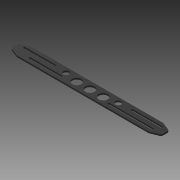
# Autodesk Inventor part: collecive_support_1
Saved by Autodesk Inventor 2015 (Build 190159000, 159)
## iProperties
Created: 2022-11-07
Part Number: collecive_support_1
Material: Generic
Document SubType Name: Modeling
Designer: Pavel Brodský
Density: 1 g/cm^3
Appearance: Default
Author: Pavel Brodský
Autodesk Inventor part; units mm, degrees
ref_plane "YZ Plane" through (0, 0, 0) normal (1, 0, 0) x (0, 1, 0)
ref_plane "XZ Plane" through (0, 0, 0) normal (0, 1, 0) x (-1, 0, 0)
ref_plane "XY Plane" through (0, 0, 0) normal (0, 0, 1) x (1, 0, 0)
sketch "Náčrt1" plane through (0, 0, 0) normal (0, 0, 1) x (1, 0, 0)
  line L0 (25.9629, 0) -> (384.0371, 0)
  line L1 (410, 13.3852) -> (410, 26.6148)
  line L2 (384.0371, 40) -> (25.9629, 40)
  line L3 (0, 26.6148) -> (0, 13.3852)
  line L4 (24.106, 39.6424) -> (3.143, 31.2572)
  line L5 (24.106, 0.3576) -> (3.143, 8.7428)
  line L6 (385.894, 0.3576) -> (406.857, 8.7428)
  line L7 (385.894, 39.6424) -> (406.857, 31.2572)
  line L8 (205, 0) -> (205, 122.739) construction
  line L9 (0, 20) -> (410, 20) construction
  circle A0 centre (205, 20) radius 12.5
  circle A1 centre (241, 20) radius 12.5
  circle A2 centre (169, 20) radius 12.5
  circle A3 centre (134, 26) radius 8
  circle A4 centre (276, 26) radius 8
  arc A5 (385.894, 39.6424) -> (384.0371, 40) centre (384.0371, 35) ccw
  arc A6 (410, 26.6148) -> (406.857, 31.2572) centre (405, 26.6148) ccw
  arc A7 (406.857, 8.7428) -> (410, 13.3852) centre (405, 13.3852) ccw
  arc A8 (384.0371, 0) -> (385.894, 0.3576) centre (384.0371, 5) ccw
  arc A9 (24.106, 0.3576) -> (25.9629, 0) centre (25.9629, 5) ccw
  arc A10 (0, 13.3852) -> (3.143, 8.7428) centre (5, 13.3852) ccw
  arc A11 (3.143, 31.2572) -> (0, 26.6148) centre (5, 26.6148) ccw
  arc A12 (25.9629, 40) -> (24.106, 39.6424) centre (25.9629, 35) ccw
  arc A13 (17.5, 31) -> (17.5, 26) centre (17.5, 28.5) ccw
  arc A14 (101.5, 26) -> (101.5, 31) centre (101.5, 28.5) ccw
  line L10 (17.5, 31) -> (101.5, 31)
  line L11 (17.5, 26) -> (101.5, 26)
  arc A15 (50, 14) -> (50, 9) centre (50, 11.5) ccw
  arc A16 (134, 9) -> (134, 14) centre (134, 11.5) ccw
  line L12 (50, 14) -> (134, 14)
  line L13 (50, 9) -> (134, 9)
  arc A17 (311.5, 31) -> (311.5, 26) centre (311.5, 28.5) ccw
  arc A18 (392.5, 26) -> (392.5, 31) centre (392.5, 28.5) ccw
  arc A19 (264.5, 14) -> (264.5, 9) centre (264.5, 11.5) ccw
  arc A20 (384.5, 9) -> (384.5, 14) centre (384.5, 11.5) ccw
  line L14 (311.5, 31) -> (392.5, 31)
  line L15 (311.5, 26) -> (392.5, 26)
  line L16 (264.5, 14) -> (384.5, 14)
  line L17 (264.5, 9) -> (384.5, 9)
  point P0 (0, 0)
  point P1 (410, 40)
  point P2 (410, 0)
  point P3 (0, 40)
  point P4 (25, 40)
  point P5 (0, 30)
  point P6 (25, 0)
  point P7 (0, 10)
  point P8 (385, 0)
  point P9 (410, 10)
  point P10 (385, 40)
  point P11 (410, 30)
  dimension "d0" = 40
  dimension "d1" = 410
  dimension "d2" = 25
  dimension "d3" = 10
  dimension "d4" = 25
  dimension "d5" = 10
  dimension "d6" = 25
  dimension "d7" = 10
  dimension "d8" = 25
  dimension "d9" = 10
  dimension "d10" = 25
  dimension "d11" = 25
  dimension "d12" = 25
  dimension "d13" = 36
  dimension "d14" = 36
  dimension "d15" = 16
  dimension "d16" = 14
  dimension "d17" = 35
  dimension "d18" = 5
  dimension "d19" = 5
  dimension "d20" = 5
  dimension "d21" = 84
  dimension "d22" = 17.5
  dimension "d23" = 9
  dimension "d24" = 5
  dimension "d25" = 5
  dimension "d26" = 84
  dimension "d27" = 9
  dimension "d28" = 50
  dimension "d29" = 5
  dimension "d30" = 5
  dimension "d31" = 5
  dimension "d32" = 5
  dimension "d33" = 9
  dimension "d34" = 81
  dimension "d35" = 17.5
  dimension "d36" = 120
  dimension "d37" = 25.5
  dimension "d38" = 11.5
  constraints: 36 end point, 32 point on circle, 29 tangent, 26 point on line, 21 centre point, 7 equal radius, 4 horizontal alignment, 4 midpoint, 4 parallel, 2 horizontal, 1 perpendicular, 1 symmetric about line, 1 vertical, 1 other
  measures "d0" distance between parallel lines of L0 L2
  measures "d1" distance between parallel lines of L3 L1
  measures "d2" distance of point (25, 40) point (0, 40)
  measures "d3" distance of point (0, 30) point (0, 40)
  measures "d4" distance of point (25, 0) point (0, 0)
  measures "d5" distance of point (0, 10) point (0, 0)
  measures "d6" distance of point (385, 0) point (410, 0)
  measures "d7" distance of point (410, 10) point (410, 0)
  measures "d8" distance of point (385, 40) point (410, 40)
  measures "d9" distance of point (410, 30) point (410, 40)
  measures "d10" diameter of A0
  measures "d11" diameter of A1
  measures "d12" diameter of A2
  measures "d13" distance of A1.centre A0.centre
  measures "d14" distance of A2.centre A0.centre
  measures "d15" diameter of A3
  measures "d16" distance from line of L2 A3.centre
  measures "d17" horizontal distance of A2.centre A3.centre
  measures "d18" radius of A5
  measures "d19" diameter of A13
  measures "d20" diameter of A14
  measures "d21" distance of A14.centre A13.centre
  measures "d22" distance from line of A13.centre L3
  measures "d23" distance between parallel lines of L2 L10
  measures "d24" diameter of A15
  measures "d25" diameter of A16
  measures "d26" distance of A16.centre A15.centre
  measures "d27" distance between parallel lines of L0 L13
  measures "d28" distance from line of L3 A15.centre
  measures "d29" diameter of A17
  measures "d30" diameter of A18
  measures "d31" diameter of A19
  measures "d32" diameter of A20
  measures "d33" distance between parallel lines of L2 L14
  measures "d34" distance of A18.centre A17.centre
  measures "d35" distance from line of L1 A18.centre
  measures "d36" distance of A20.centre A19.centre
  measures "d37" distance from line of L1 A20.centre
  measures "d38" distance from line of L0 A19.centre
extrude "Vysunutí1" add sketch "Náčrt1" along normal blind 4
equation "\"d4\" = d2"
equation "\"d5\" = d3"
equation "\"d6\" = d2"
equation "\"d7\" = d3"
equation "\"d8\" = d2"
equation "\"d9\" = d3"
equation "\"d11\" = d10"
equation "\"d12\" = d10"
equation "\"d14\" = d13"
equation "\"d20\" = d19"
equation "\"d25\" = d24"
equation "\"d33\" = d23"
